Autodesk Fusion 360 part; units mm, degrees
(part 2 of 10)
sketch "10 Node register socket sketch (7) (3)" plane through (0, 0, 5) normal (0, 0, 1) x (1, 0, 0) in component "Panel upper left"
  circle A0 centre (115, 223) radius 1.2
  dimension "d518" = 115
  dimension "d519" = 223
  dimension "d520" = 2.4
  measures "d518" horizontal distance of origin A0.centre
  measures "d519" vertical distance of origin A0.centre
  measures "d520" diameter of A0
extrude "10 Node register socket (7)''" cut sketch "10 Node register socket sketch (7) (3)" against normal blind 1 bodies 3 in component "Panel upper left"
ref_plane "WorkPlane11" through (0, 0, 5) normal (0, 0, 1) x (1, 0, 0) in component "Panel upper left"
sketch "10 Node register socket sketch (8) (3)" plane through (0, 0, 5) normal (0, 0, 1) x (1, 0, 0) in component "Panel upper left"
  circle A0 centre (115, 233) radius 1.2
  dimension "d525" = 115
  dimension "d526" = 233
  dimension "d527" = 2.4
  measures "d525" horizontal distance of origin A0.centre
  measures "d526" vertical distance of origin A0.centre
  measures "d527" diameter of A0
extrude "10 Node register socket (8)''" cut sketch "10 Node register socket sketch (8) (3)" against normal blind 1 bodies 3 in component "Panel upper left"
sketch "01 Panel blank sketch (4)" plane through (0, 0, 0) normal (0, 0, 1) x (1, 0, 0) in component "Panel upper right"
  line L0 (120.1, 120.1) -> (239.9, 120.1)
  line L1 (239.9, 120.1) -> (239.9, 239.9)
  line L2 (239.9, 239.9) -> (120.1, 239.9)
  line L3 (120.1, 239.9) -> (120.1, 120.1)
  dimension "d534" = 120.1
  dimension "d535" = 120.1
  dimension "d536" = 119.8
  dimension "d537" = 119.8
  constraint horizontal L0
  constraint vertical L1
  constraint horizontal L2
  constraint vertical L3
  measures "d534" horizontal distance of origin L0.start
  measures "d535" vertical distance of origin L0.start
  measures "d536" horizontal distance of L0.start L0.end
  measures "d537" vertical distance of L0.end L1.end
extrude "01 Panel blank'''" add sketch "01 Panel blank sketch (4)" along normal blind 5 separate body makes body 4 in component "Panel upper right"
fillet "02 Rounded exterior corners'''" radius 6 1 edges at (239.9, 239.9, 2.5) on bodies 4 in component "Panel upper right"
sketch "03 A main constrained seed (4)" plane through (0, 0, 0) normal (0, 0, 1) x (1, 0, 0) in component "Panel upper right"
  line L0 (147.5, 125) -> (147.5, 135)
  arc A0 (147.5, 135) -> (142.5, 135) centre (145, 135) ccw
  line L1 (142.5, 135) -> (142.5, 125)
  arc A1 (142.5, 125) -> (147.5, 125) centre (145, 125) ccw
  line L2 (145, 125) -> (145, 135) construction
  line L3 (145, 125) -> (155, 125) construction
  dimension "d542" = 5
  dimension "d543" = 10
  dimension "d544" = 90
  dimension "d545" = 10
  dimension "d546" = 145
  dimension "d547" = 125
  constraint tangent L0 A0
  constraint tangent A0 L1
  constraint tangent L1 A1
  constraint tangent L0 A1
  constraint parallel L0 L1
  constraint horizontal L3
  measures "d542" diameter of A0
  measures "d543" distance of A1.centre A0.centre
  measures "d544" angle of L2 L3
  measures "d545" horizontal distance of A1.centre L3.end
  measures "d546" horizontal distance of origin A1.centre
  measures "d547" vertical distance of origin A1.centre
extrude "03 A main through cut'''" cut sketch "03 A main constrained seed (4)" along normal blind 5 bodies 4 in component "Panel upper right"
pattern_linear "03 A main lattice'''" count 4 spacing 20 along (1, 0, 0) count 5 spacing 20 along (0, 1, 0) of "03 A main through cut'''" in component "Panel upper right"
sketch "04 A end strip constrained seed (4)" plane through (0, 0, 0) normal (0, 0, 1) x (1, 0, 0) in component "Panel upper right"
  line L0 (127.5, 145) -> (127.5, 155)
  arc A0 (127.5, 155) -> (122.5, 155) centre (125, 155) ccw
  line L1 (122.5, 155) -> (122.5, 145)
  arc A1 (122.5, 145) -> (127.5, 145) centre (125, 145) ccw
  line L2 (125, 145) -> (125, 155) construction
  line L3 (125, 145) -> (135, 145) construction
  dimension "d554" = 5
  dimension "d555" = 10
  dimension "d556" = 90
  dimension "d557" = 10
  dimension "d558" = 125
  dimension "d559" = 145
  constraint tangent L0 A0
  constraint tangent A0 L1
  constraint tangent L1 A1
  constraint tangent L0 A1
  constraint parallel L0 L1
  constraint horizontal L3
  measures "d554" diameter of A0
  measures "d555" distance of A1.centre A0.centre
  measures "d556" angle of L2 L3
  measures "d557" horizontal distance of A1.centre L3.end
  measures "d558" horizontal distance of origin A1.centre
  measures "d559" vertical distance of origin A1.centre
extrude "04 A end strip through cut'''" cut sketch "04 A end strip constrained seed (4)" along normal blind 5 bodies 4 in component "Panel upper right"
pattern_linear "04 A end strip lattice'''" count 1 spacing 20 along (1, 0, 0) count 3 spacing 20 along (0, 1, 0) of "04 A end strip through cut'''" in component "Panel upper right"
sketch "05 B main constrained seed (4)" plane through (0, 0, 0) normal (0, 0, 1) x (1, 0, 0) in component "Panel upper right"
  line L0 (137.5, 115) -> (137.5, 125)
  arc A0 (137.5, 125) -> (132.5, 125) centre (135, 125) ccw
  line L1 (132.5, 125) -> (132.5, 115)
  arc A1 (132.5, 115) -> (137.5, 115) centre (135, 115) ccw
  line L2 (135, 115) -> (135, 125) construction
  line L3 (135, 115) -> (145, 115) construction
  dimension "d566" = 5
  dimension "d567" = 10
  dimension "d568" = 90
  dimension "d569" = 10
  dimension "d570" = 135
  dimension "d571" = 115
  constraint tangent L0 A0
  constraint tangent A0 L1
  constraint tangent L1 A1
  constraint tangent L0 A1
  constraint parallel L0 L1
  constraint horizontal L3
  measures "d566" diameter of A0
  measures "d567" distance of A1.centre A0.centre
  measures "d568" angle of L2 L3
  measures "d569" horizontal distance of A1.centre L3.end
  measures "d570" horizontal distance of origin A1.centre
  measures "d571" vertical distance of origin A1.centre
extrude "05 B main through cut'''" cut sketch "05 B main constrained seed (4)" along normal blind 5 bodies 4 in component "Panel upper right"
pattern_linear "05 B main lattice'''" count 4 spacing 20 along (1, 0, 0) count 6 spacing 20 along (0, 1, 0) of "05 B main through cut'''" in component "Panel upper right"
sketch "06 B end strip constrained seed (4)" plane through (0, 0, 0) normal (0, 0, 1) x (1, 0, 0) in component "Panel upper right"
  line L0 (217.5, 135) -> (217.5, 145)
  arc A0 (217.5, 145) -> (212.5, 145) centre (215, 145) ccw
  line L1 (212.5, 145) -> (212.5, 135)
  arc A1 (212.5, 135) -> (217.5, 135) centre (215, 135) ccw
  line L2 (215, 135) -> (215, 145) construction
  line L3 (215, 135) -> (225, 135) construction
  dimension "d578" = 5
  dimension "d579" = 10
  dimension "d580" = 90
  dimension "d581" = 10
  dimension "d582" = 215
  dimension "d583" = 135
  constraint tangent L0 A0
  constraint tangent A0 L1
  constraint tangent L1 A1
  constraint tangent L0 A1
  constraint parallel L0 L1
  constraint horizontal L3
  measures "d578" diameter of A0
  measures "d579" distance of A1.centre A0.centre
  measures "d580" angle of L2 L3
  measures "d581" horizontal distance of A1.centre L3.end
  measures "d582" horizontal distance of origin A1.centre
  measures "d583" vertical distance of origin A1.centre
extrude "06 B end strip through cut'''" cut sketch "06 B end strip constrained seed (4)" along normal blind 5 bodies 4 in component "Panel upper right"
pattern_linear "06 B end strip lattice'''" count 1 spacing 20 along (1, 0, 0) count 4 spacing 20 along (0, 1, 0) of "06 B end strip through cut'''" in component "Panel upper right"
sketch "07 Shared node clearance sketch (6)" plane through (0, 0, 0) normal (0, 0, 1) x (1, 0, 0) in component "Panel upper right"
  circle A0 centre (120, 120) radius 4.2
  dimension "d590" = 120
  dimension "d591" = 120
  dimension "d592" = 8.4
  measures "d590" horizontal distance of origin A0.centre
  measures "d591" vertical distance of origin A0.centre
  measures "d592" diameter of A0
extrude "07 Shared node clearance'''" cut sketch "07 Shared node clearance sketch (6)" along normal blind 5 bodies 4 in component "Panel upper right"
sketch "07 Shared node clearance sketch (1) (4)" plane through (0, 0, 0) normal (0, 0, 1) x (1, 0, 0) in component "Panel upper right"
  circle A0 centre (120, 228) radius 4.2
  dimension "d595" = 120
  dimension "d596" = 228
  dimension "d597" = 8.4
  measures "d595" horizontal distance of origin A0.centre
  measures "d596" vertical distance of origin A0.centre
  measures "d597" diameter of A0
extrude "07 Shared node clearance (1)'''" cut sketch "07 Shared node clearance sketch (1) (4)" along normal blind 5 bodies 4 in component "Panel upper right"
sketch "07 Shared node clearance sketch (2) (4)" plane through (0, 0, 0) normal (0, 0, 1) x (1, 0, 0) in component "Panel upper right"
  circle A0 centre (228, 120) radius 4.2
  dimension "d600" = 228
  dimension "d601" = 120
  dimension "d602" = 8.4
  measures "d600" horizontal distance of origin A0.centre
  measures "d601" vertical distance of origin A0.centre
  measures "d602" diameter of A0
extrude "07 Shared node clearance (2)'''" cut sketch "07 Shared node clearance sketch (2) (4)" along normal blind 5 bodies 4 in component "Panel upper right"
sketch "07 Shared node clearance sketch (3) (4)" plane through (0, 0, 0) normal (0, 0, 1) x (1, 0, 0) in component "Panel upper right"
  circle A0 centre (228, 228) radius 4.2
  dimension "d605" = 228
  dimension "d606" = 228
  dimension "d607" = 8.4
  measures "d605" horizontal distance of origin A0.centre
  measures "d606" vertical distance of origin A0.centre
  measures "d607" diameter of A0
extrude "07 Shared node clearance (3)'''" cut sketch "07 Shared node clearance sketch (3) (4)" along normal blind 5 bodies 4 in component "Panel upper right"
fillet "08 Rounded slot entrances and face edges'''" radius 0.4 2 faces at (232.4333, 176.3333, 0) (232.4333, 176.3333, 0) on bodies 4 in component "Panel upper right"
ref_plane "WorkPlane1" through (0, 0, 5) normal (0, 0, 1) x (1, 0, 0) in component "Panel upper right"
sketch "09 Blind rear key socket sketch (4)" plane through (0, 0, 5) normal (0, 0, 1) x (1, 0, 0) in component "Panel upper right"
  circle A0 centre (125, 200) radius 1.7
  dimension "d614" = 125
  dimension "d615" = 200
  dimension "d616" = 3.4
  measures "d614" horizontal distance of origin A0.centre
  measures "d615" vertical distance of origin A0.centre
  measures "d616" diameter of A0
ref_plane "WorkPlane2" through (0, 0, 5) normal (0, 0, 1) x (1, 0, 0) in component "Panel upper right"
sketch "09 Blind rear key socket sketch (1) (4)" plane through (0, 0, 5) normal (0, 0, 1) x (1, 0, 0) in component "Panel upper right"
  circle A0 centre (190, 125) radius 1.7
  dimension "d621" = 190
  dimension "d622" = 125
  dimension "d623" = 3.4
  measures "d621" horizontal distance of origin A0.centre
  measures "d622" vertical distance of origin A0.centre
  measures "d623" diameter of A0
ref_plane "WorkPlane3" through (0, 0, 5) normal (0, 0, 1) x (1, 0, 0) in component "Panel upper right"
sketch "10 Node register socket sketch (11)" plane through (0, 0, 5) normal (0, 0, 1) x (1, 0, 0) in component "Panel upper right"
  circle A0 centre (125, 125) radius 1.2
  dimension "d628" = 125
  dimension "d629" = 125
  dimension "d630" = 2.4
  measures "d628" horizontal distance of origin A0.centre
  measures "d629" vertical distance of origin A0.centre
  measures "d630" diameter of A0
extrude "10 Node register socket'''" cut sketch "10 Node register socket sketch (11)" against normal blind 1 bodies 4 in component "Panel upper right"
ref_plane "WorkPlane4" through (0, 0, 5) normal (0, 0, 1) x (1, 0, 0) in component "Panel upper right"
sketch "10 Node register socket sketch (1) (4)" plane through (0, 0, 5) normal (0, 0, 1) x (1, 0, 0) in component "Panel upper right"
  circle A0 centre (125, 223) radius 1.2
  dimension "d635" = 125
  dimension "d636" = 223
  dimension "d637" = 2.4
  measures "d635" horizontal distance of origin A0.centre
  measures "d636" vertical distance of origin A0.centre
  measures "d637" diameter of A0
extrude "10 Node register socket (1)'''" cut sketch "10 Node register socket sketch (1) (4)" against normal blind 1 bodies 4 in component "Panel upper right"
ref_plane "WorkPlane5" through (0, 0, 5) normal (0, 0, 1) x (1, 0, 0) in component "Panel upper right"
sketch "10 Node register socket sketch (2) (4)" plane through (0, 0, 5) normal (0, 0, 1) x (1, 0, 0) in component "Panel upper right"
  circle A0 centre (125, 233) radius 1.2
  dimension "d642" = 125
  dimension "d643" = 233
  dimension "d644" = 2.4
  measures "d642" horizontal distance of origin A0.centre
  measures "d643" vertical distance of origin A0.centre
  measures "d644" diameter of A0
extrude "10 Node register socket (2)'''" cut sketch "10 Node register socket sketch (2) (4)" against normal blind 1 bodies 4 in component "Panel upper right"
ref_plane "WorkPlane6" through (0, 0, 5) normal (0, 0, 1) x (1, 0, 0) in component "Panel upper right"
sketch "10 Node register socket sketch (3) (4)" plane through (0, 0, 5) normal (0, 0, 1) x (1, 0, 0) in component "Panel upper right"
  circle A0 centre (223, 125) radius 1.2
  dimension "d649" = 223
  dimension "d650" = 125
  dimension "d651" = 2.4
  measures "d649" horizontal distance of origin A0.centre
  measures "d650" vertical distance of origin A0.centre
  measures "d651" diameter of A0
extrude "10 Node register socket (3)'''" cut sketch "10 Node register socket sketch (3) (4)" against normal blind 1 bodies 4 in component "Panel upper right"
ref_plane "WorkPlane7" through (0, 0, 5) normal (0, 0, 1) x (1, 0, 0) in component "Panel upper right"
sketch "10 Node register socket sketch (4) (4)" plane through (0, 0, 5) normal (0, 0, 1) x (1, 0, 0) in component "Panel upper right"
  circle A0 centre (233, 125) radius 1.2
  dimension "d656" = 233
  dimension "d657" = 125
  dimension "d658" = 2.4
  measures "d656" horizontal distance of origin A0.centre
  measures "d657" vertical distance of origin A0.centre
  measures "d658" diameter of A0
extrude "10 Node register socket (4)'''" cut sketch "10 Node register socket sketch (4) (4)" against normal blind 1 bodies 4 in component "Panel upper right"
ref_plane "WorkPlane8" through (0, 0, 5) normal (0, 0, 1) x (1, 0, 0) in component "Panel upper right"
sketch "10 Node register socket sketch (5) (4)" plane through (0, 0, 5) normal (0, 0, 1) x (1, 0, 0) in component "Panel upper right"
  circle A0 centre (223, 223) radius 1.2
  dimension "d663" = 223
  dimension "d664" = 223
  dimension "d665" = 2.4
  measures "d663" horizontal distance of origin A0.centre
  measures "d664" vertical distance of origin A0.centre
  measures "d665" diameter of A0
extrude "10 Node register socket (5)'''" cut sketch "10 Node register socket sketch (5) (4)" against normal blind 1 bodies 4 in component "Panel upper right"
ref_plane "WorkPlane9" through (0, 0, 5) normal (0, 0, 1) x (1, 0, 0) in component "Panel upper right"
sketch "10 Node register socket sketch (6) (4)" plane through (0, 0, 5) normal (0, 0, 1) x (1, 0, 0) in component "Panel upper right"
  circle A0 centre (223, 233) radius 1.2
  dimension "d670" = 223
  dimension "d671" = 233
  dimension "d672" = 2.4
  measures "d670" horizontal distance of origin A0.centre
  measures "d671" vertical distance of origin A0.centre
  measures "d672" diameter of A0
extrude "10 Node register socket (6)'''" cut sketch "10 Node register socket sketch (6) (4)" against normal blind 1 bodies 4 in component "Panel upper right"
ref_plane "WorkPlane10" through (0, 0, 5) normal (0, 0, 1) x (1, 0, 0) in component "Panel upper right"
sketch "10 Node register socket sketch (7) (4)" plane through (0, 0, 5) normal (0, 0, 1) x (1, 0, 0) in component "Panel upper right"
  circle A0 centre (233, 223) radius 1.2
  dimension "d677" = 233
  dimension "d678" = 223
  dimension "d679" = 2.4
  measures "d677" horizontal distance of origin A0.centre
  measures "d678" vertical distance of origin A0.centre
  measures "d679" diameter of A0
extrude "10 Node register socket (7)'''" cut sketch "10 Node register socket sketch (7) (4)" against normal blind 1 bodies 4 in component "Panel upper right"
ref_plane "WorkPlane11" through (0, 0, 5) normal (0, 0, 1) x (1, 0, 0) in component "Panel upper right"
sketch "10 Node register socket sketch (8) (4)" plane through (0, 0, 5) normal (0, 0, 1) x (1, 0, 0) in component "Panel upper right"
  circle A0 centre (233, 233) radius 1.2
  dimension "d684" = 233
  dimension "d685" = 233
  dimension "d686" = 2.4
  measures "d684" horizontal distance of origin A0.centre
  measures "d685" vertical distance of origin A0.centre
  measures "d686" diameter of A0
extrude "10 Node register socket (8)'''" cut sketch "10 Node register socket sketch (8) (4)" against normal blind 1 bodies 4 in component "Panel upper right"
ref_plane "WorkPlane1" through (0, 2, 0) normal (0, 1, 0) x (0, 0, 1) in component "Vertical rail 0 - measured sloped-slot approximation"
sketch "Profile blank sketch" plane through (0, 2, 0) normal (0, 1, 0) x (1, 0, 0) in component "Vertical rail 0 - measured sloped-slot approximation"
  line L0 (2, -15) -> (22, -15)
  line L1 (22, -15) -> (22, -35)
  line L2 (22, -35) -> (2, -35)
  line L3 (2, -35) -> (2, -15)
  dimension "d701" = 2
  dimension "d702" = 15
  dimension "d703" = 22
  dimension "d704" = 35
  constraint horizontal L0.start L0.end
  constraint vertical L0.end L1.end
  constraint vertical L0.start L2.end
  constraint horizontal L1.end L2.end
  measures "d701" horizontal distance of origin L0.start
  measures "d702" vertical distance of origin L0.start
  measures "d703" horizontal distance of origin L0.end
  measures "d704" vertical distance of origin L1.end
extrude "Profile blank" add sketch "Profile blank sketch" along normal blind 236 separate body makes body 5 in component "Vertical rail 0 - measured sloped-slot approximation"
ref_plane "WorkPlane2" through (0, 2, 0) normal (0, 1, 0) x (0, 0, 1) in component "Vertical rail 0 - measured sloped-slot approximation"
sketch "Sloped T channel 0 sketch" plane through (0, 2, 0) normal (0, 1, 0) x (1, 0, 0) in component "Vertical rail 0 - measured sloped-slot approximation"
  line L0 (8.86, -15) -> (8.86, -16.5)
  line L1 (8.86, -16.5) -> (6.5, -16.5)
  line L2 (6.5, -16.5) -> (6.5, -18.55)
  line L3 (6.5, -18.55) -> (9.15, -21.2)
  line L4 (9.15, -21.2) -> (14.85, -21.2)
  line L5 (14.85, -21.2) -> (17.5, -18.55)
  line L6 (17.5, -18.55) -> (17.5, -16.5)
  line L7 (17.5, -16.5) -> (15.14, -16.5)
  line L8 (15.14, -16.5) -> (15.14, -15)
  line L9 (15.14, -15) -> (8.86, -15)
  dimension "d709" = 8.86
  dimension "d710" = 15
  dimension "d711" = 16.5
  dimension "d712" = 6.5
  dimension "d713" = 18.55
  dimension "d714" = 9.15
  dimension "d715" = 21.2
  dimension "d716" = 14.85
  dimension "d717" = 17.5
  dimension "d718" = 15.14
  constraint vertical L0.start L0.end
  constraint horizontal L0.end L1.end
  constraint vertical L1.end L2.end
  constraint horizontal L3.end L4.end
  constraint horizontal L2.end L5.end
  constraint vertical L5.end L6.end
  constraint horizontal L1.end L6.end
  constraint horizontal L6.end L7.end
  constraint vertical L7.end L8.end
  constraint horizontal L0.start L8.end
  measures "d709" horizontal distance of origin L0.start
  measures "d710" vertical distance of origin L0.start
  measures "d711" vertical distance of origin L0.end
  measures "d712" horizontal distance of origin L1.end
  measures "d713" vertical distance of origin L2.end
  measures "d714" horizontal distance of origin L3.end
  measures "d715" vertical distance of origin L3.end
  measures "d716" horizontal distance of origin L4.end
  measures "d717" horizontal distance of origin L5.end
  measures "d718" horizontal distance of origin L7.end
extrude "Sloped T channel 0" cut sketch "Sloped T channel 0 sketch" along normal blind 236 bodies 5 in component "Vertical rail 0 - measured sloped-slot approximation"
ref_plane "WorkPlane3" through (0, 2, 0) normal (0, 1, 0) x (0, 0, 1) in component "Vertical rail 0 - measured sloped-slot approximation"
sketch "Sloped T channel 1 sketch" plane through (0, 2, 0) normal (0, 1, 0) x (1, 0, 0) in component "Vertical rail 0 - measured sloped-slot approximation"
  line L0 (22, -21.86) -> (20.5, -21.86)
  line L1 (20.5, -21.86) -> (20.5, -19.5)
  line L2 (20.5, -19.5) -> (18.45, -19.5)
  line L3 (18.45, -19.5) -> (15.8, -22.15)
  line L4 (15.8, -22.15) -> (15.8, -27.85)
  line L5 (15.8, -27.85) -> (18.45, -30.5)
  line L6 (18.45, -30.5) -> (20.5, -30.5)
  line L7 (20.5, -30.5) -> (20.5, -28.14)
  line L8 (20.5, -28.14) -> (22, -28.14)
  line L9 (22, -28.14) -> (22, -21.86)
  dimension "d723" = 22
  dimension "d724" = 21.86
  dimension "d725" = 20.5
  dimension "d726" = 19.5
  dimension "d727" = 18.45
  dimension "d728" = 15.8
  dimension "d729" = 22.15
  dimension "d730" = 27.85
  dimension "d731" = 30.5
  dimension "d732" = 28.14
  constraint horizontal L0.start L0.end
  constraint vertical L0.end L1.end
  constraint horizontal L1.end L2.end
  constraint vertical L3.end L4.end
  constraint vertical L2.end L5.end
  constraint vertical L1.end L6.end
  constraint horizontal L5.end L6.end
  constraint vertical L6.end L7.end
  constraint vertical L0.start L8.end
  constraint horizontal L7.end L8.end
  measures "d723" horizontal distance of origin L0.start
  measures "d724" vertical distance of origin L0.start
  measures "d725" horizontal distance of origin L0.end
  measures "d726" vertical distance of origin L1.end
  measures "d727" horizontal distance of origin L2.end
  measures "d728" horizontal distance of origin L3.end
  measures "d729" vertical distance of origin L3.end
  measures "d730" vertical distance of origin L4.end
  measures "d731" vertical distance of origin L5.end
  measures "d732" vertical distance of origin L7.end
extrude "Sloped T channel 1" cut sketch "Sloped T channel 1 sketch" along normal blind 236 bodies 5 in component "Vertical rail 0 - measured sloped-slot approximation"
ref_plane "WorkPlane4" through (0, 2, 0) normal (0, 1, 0) x (0, 0, 1) in component "Vertical rail 0 - measured sloped-slot approximation"
sketch "Sloped T channel 2 sketch" plane through (0, 2, 0) normal (0, 1, 0) x (1, 0, 0) in component "Vertical rail 0 - measured sloped-slot approximation"
  line L0 (15.14, -35) -> (15.14, -33.5)
  line L1 (15.14, -33.5) -> (17.5, -33.5)
  line L2 (17.5, -33.5) -> (17.5, -31.45)
  line L3 (17.5, -31.45) -> (14.85, -28.8)
  line L4 (14.85, -28.8) -> (9.15, -28.8)
  line L5 (9.15, -28.8) -> (6.5, -31.45)
  line L6 (6.5, -31.45) -> (6.5, -33.5)
  line L7 (6.5, -33.5) -> (8.86, -33.5)
  line L8 (8.86, -33.5) -> (8.86, -35)
  line L9 (8.86, -35) -> (15.14, -35)
  dimension "d737" = 15.14
  dimension "d738" = 35
  dimension "d739" = 33.5
  dimension "d740" = 17.5
  dimension "d741" = 31.45
  dimension "d742" = 14.85
  dimension "d743" = 28.8
  dimension "d744" = 9.15
  dimension "d745" = 6.5
  dimension "d746" = 8.86
  constraint vertical L0.start L0.end
  constraint horizontal L0.end L1.end
  constraint vertical L1.end L2.end
  constraint horizontal L3.end L4.end
  constraint horizontal L2.end L5.end
  constraint vertical L5.end L6.end
  constraint horizontal L1.end L6.end
  constraint horizontal L6.end L7.end
  constraint vertical L7.end L8.end
  constraint horizontal L0.start L8.end
  measures "d737" horizontal distance of origin L0.start
  measures "d738" vertical distance of origin L0.start
  measures "d739" vertical distance of origin L0.end
  measures "d740" horizontal distance of origin L1.end
  measures "d741" vertical distance of origin L2.end
  measures "d742" horizontal distance of origin L3.end
  measures "d743" vertical distance of origin L3.end
  measures "d744" horizontal distance of origin L4.end
  measures "d745" horizontal distance of origin L5.end
  measures "d746" horizontal distance of origin L7.end
extrude "Sloped T channel 2" cut sketch "Sloped T channel 2 sketch" along normal blind 236 bodies 5 in component "Vertical rail 0 - measured sloped-slot approximation"
ref_plane "WorkPlane5" through (0, 2, 0) normal (0, 1, 0) x (0, 0, 1) in component "Vertical rail 0 - measured sloped-slot approximation"
sketch "Sloped T channel 3 sketch" plane through (0, 2, 0) normal (0, 1, 0) x (1, 0, 0) in component "Vertical rail 0 - measured sloped-slot approximation"
  line L0 (2, -28.14) -> (3.5, -28.14)
  line L1 (3.5, -28.14) -> (3.5, -30.5)
  line L2 (3.5, -30.5) -> (5.55, -30.5)
  line L3 (5.55, -30.5) -> (8.2, -27.85)
  line L4 (8.2, -27.85) -> (8.2, -22.15)
  line L5 (8.2, -22.15) -> (5.55, -19.5)
  line L6 (5.55, -19.5) -> (3.5, -19.5)
  line L7 (3.5, -19.5) -> (3.5, -21.86)
  line L8 (3.5, -21.86) -> (2, -21.86)
  line L9 (2, -21.86) -> (2, -28.14)
  dimension "d751" = 2
  dimension "d752" = 28.14
  dimension "d753" = 3.5
  dimension "d754" = 30.5
  dimension "d755" = 5.55
  dimension "d756" = 8.2
  dimension "d757" = 27.85
  dimension "d758" = 22.15
  dimension "d759" = 19.5
  dimension "d760" = 21.86
  constraint horizontal L0.start L0.end
  constraint vertical L0.end L1.end
  constraint horizontal L1.end L2.end
  constraint vertical L3.end L4.end
  constraint vertical L2.end L5.end
  constraint vertical L1.end L6.end
  constraint horizontal L5.end L6.end
  constraint vertical L6.end L7.end
  constraint vertical L0.start L8.end
  constraint horizontal L7.end L8.end
  measures "d751" horizontal distance of origin L0.start
  measures "d752" vertical distance of origin L0.start
  measures "d753" horizontal distance of origin L0.end
  measures "d754" vertical distance of origin L1.end
  measures "d755" horizontal distance of origin L2.end
  measures "d756" horizontal distance of origin L3.end
  measures "d757" vertical distance of origin L3.end
  measures "d758" vertical distance of origin L4.end
  measures "d759" vertical distance of origin L5.end
  measures "d760" vertical distance of origin L7.end
extrude "Sloped T channel 3" cut sketch "Sloped T channel 3 sketch" along normal blind 236 bodies 5 in component "Vertical rail 0 - measured sloped-slot approximation"
ref_plane "WorkPlane6" through (0, 2, 0) normal (0, 1, 0) x (0, 0, 1) in component "Vertical rail 0 - measured sloped-slot approximation"
sketch "Reference center bore sketch" plane through (0, 2, 0) normal (0, 1, 0) x (1, 0, 0) in component "Vertical rail 0 - measured sloped-slot approximation"
  circle A0 centre (12, -25) radius 2.5
  dimension "d765" = 12
  dimension "d766" = 25
  dimension "d767" = 5
  measures "d765" horizontal distance of origin A0.centre
  measures "d766" vertical distance of origin A0.centre
  measures "d767" diameter of A0
extrude "Reference center bore" cut sketch "Reference center bore sketch" along normal blind 236 bodies 5 in component "Vertical rail 0 - measured sloped-slot approximation"
ref_plane "WorkPlane1" through (0, 2, 0) normal (0, 1, 0) x (0, 0, 1) in component "Vertical rail 1 - measured sloped-slot approximation"
sketch "Profile blank sketch (2)" plane through (0, 2, 0) normal (0, 1, 0) x (1, 0, 0) in component "Vertical rail 1 - measured sloped-slot approximation"
  line L0 (110, -15) -> (130, -15)
  line L1 (130, -15) -> (130, -35)
  line L2 (130, -35) -> (110, -35)
  line L3 (110, -35) -> (110, -15)
  dimension "d772" = 110
  dimension "d773" = 15
  dimension "d774" = 130
  dimension "d775" = 35
  constraint horizontal L0.start L0.end
  constraint vertical L0.end L1.end
  constraint vertical L0.start L2.end
  constraint horizontal L1.end L2.end
  measures "d772" horizontal distance of origin L0.start
  measures "d773" vertical distance of origin L0.start
  measures "d774" horizontal distance of origin L0.end
  measures "d775" vertical distance of origin L1.end
extrude "Profile blank'" add sketch "Profile blank sketch (2)" along normal blind 236 separate body makes body 6 in component "Vertical rail 1 - measured sloped-slot approximation"
ref_plane "WorkPlane2" through (0, 2, 0) normal (0, 1, 0) x (0, 0, 1) in component "Vertical rail 1 - measured sloped-slot approximation"
sketch "Sloped T channel 0 sketch (2)" plane through (0, 2, 0) normal (0, 1, 0) x (1, 0, 0) in component "Vertical rail 1 - measured sloped-slot approximation"
  line L0 (116.86, -15) -> (116.86, -16.5)
  line L1 (116.86, -16.5) -> (114.5, -16.5)
  line L2 (114.5, -16.5) -> (114.5, -18.55)
  line L3 (114.5, -18.55) -> (117.15, -21.2)
  line L4 (117.15, -21.2) -> (122.85, -21.2)
  line L5 (122.85, -21.2) -> (125.5, -18.55)
  line L6 (125.5, -18.55) -> (125.5, -16.5)
  line L7 (125.5, -16.5) -> (123.14, -16.5)
  line L8 (123.14, -16.5) -> (123.14, -15)
  line L9 (123.14, -15) -> (116.86, -15)
  dimension "d780" = 116.86
  dimension "d781" = 15
  dimension "d782" = 16.5
  dimension "d783" = 114.5
  dimension "d784" = 18.55
  dimension "d785" = 117.15
  dimension "d786" = 21.2
  dimension "d787" = 122.85
  dimension "d788" = 125.5
  dimension "d789" = 123.14
  constraint vertical L0.start L0.end
  constraint horizontal L0.end L1.end
  constraint vertical L1.end L2.end
  constraint horizontal L3.end L4.end
  constraint horizontal L2.end L5.end
  constraint vertical L5.end L6.end
  constraint horizontal L1.end L6.end
  constraint horizontal L6.end L7.end
  constraint vertical L7.end L8.end
  constraint horizontal L0.start L8.end
  measures "d780" horizontal distance of origin L0.start
  measures "d781" vertical distance of origin L0.start
  measures "d782" vertical distance of origin L0.end
  measures "d783" horizontal distance of origin L1.end
  measures "d784" vertical distance of origin L2.end
  measures "d785" horizontal distance of origin L3.end
  measures "d786" vertical distance of origin L3.end
  measures "d787" horizontal distance of origin L4.end
  measures "d788" horizontal distance of origin L5.end
  measures "d789" horizontal distance of origin L7.end
extrude "Sloped T channel 0'" cut sketch "Sloped T channel 0 sketch (2)" along normal blind 236 bodies 6 in component "Vertical rail 1 - measured sloped-slot approximation"
ref_plane "WorkPlane3" through (0, 2, 0) normal (0, 1, 0) x (0, 0, 1) in component "Vertical rail 1 - measured sloped-slot approximation"
sketch "Sloped T channel 1 sketch (2)" plane through (0, 2, 0) normal (0, 1, 0) x (1, 0, 0) in component "Vertical rail 1 - measured sloped-slot approximation"
  line L0 (130, -21.86) -> (128.5, -21.86)
  line L1 (128.5, -21.86) -> (128.5, -19.5)
  line L2 (128.5, -19.5) -> (126.45, -19.5)
  line L3 (126.45, -19.5) -> (123.8, -22.15)
  line L4 (123.8, -22.15) -> (123.8, -27.85)
  line L5 (123.8, -27.85) -> (126.45, -30.5)
  line L6 (126.45, -30.5) -> (128.5, -30.5)
  line L7 (128.5, -30.5) -> (128.5, -28.14)
  line L8 (128.5, -28.14) -> (130, -28.14)
  line L9 (130, -28.14) -> (130, -21.86)
  dimension "d794" = 130
  dimension "d795" = 21.86
  dimension "d796" = 128.5
  dimension "d797" = 19.5
  dimension "d798" = 126.45
  dimension "d799" = 123.8
  dimension "d800" = 22.15
  dimension "d801" = 27.85
  dimension "d802" = 30.5
  dimension "d803" = 28.14
  constraint horizontal L0.start L0.end
  constraint vertical L0.end L1.end
  constraint horizontal L1.end L2.end
  constraint vertical L3.end L4.end
  constraint vertical L2.end L5.end
  constraint vertical L1.end L6.end
  constraint horizontal L5.end L6.end
  constraint vertical L6.end L7.end
  constraint vertical L0.start L8.end
  constraint horizontal L7.end L8.end
  measures "d794" horizontal distance of origin L0.start
  measures "d795" vertical distance of origin L0.start
  measures "d796" horizontal distance of origin L0.end
  measures "d797" vertical distance of origin L1.end
  measures "d798" horizontal distance of origin L2.end
  measures "d799" horizontal distance of origin L3.end
  measures "d800" vertical distance of origin L3.end
  measures "d801" vertical distance of origin L4.end
  measures "d802" vertical distance of origin L5.end
  measures "d803" vertical distance of origin L7.end
extrude "Sloped T channel 1'" cut sketch "Sloped T channel 1 sketch (2)" along normal blind 236 bodies 6 in component "Vertical rail 1 - measured sloped-slot approximation"
ref_plane "WorkPlane4" through (0, 2, 0) normal (0, 1, 0) x (0, 0, 1) in component "Vertical rail 1 - measured sloped-slot approximation"
sketch "Sloped T channel 2 sketch (2)" plane through (0, 2, 0) normal (0, 1, 0) x (1, 0, 0) in component "Vertical rail 1 - measured sloped-slot approximation"
  line L0 (123.14, -35) -> (123.14, -33.5)
  line L1 (123.14, -33.5) -> (125.5, -33.5)
  line L2 (125.5, -33.5) -> (125.5, -31.45)
  line L3 (125.5, -31.45) -> (122.85, -28.8)
  line L4 (122.85, -28.8) -> (117.15, -28.8)
  line L5 (117.15, -28.8) -> (114.5, -31.45)
  line L6 (114.5, -31.45) -> (114.5, -33.5)
  line L7 (114.5, -33.5) -> (116.86, -33.5)
  line L8 (116.86, -33.5) -> (116.86, -35)
  line L9 (116.86, -35) -> (123.14, -35)
  dimension "d808" = 123.14
  dimension "d809" = 35
  dimension "d810" = 33.5
  dimension "d811" = 125.5
  dimension "d812" = 31.45
  dimension "d813" = 122.85
  dimension "d814" = 28.8
  dimension "d815" = 117.15
  dimension "d816" = 114.5
  dimension "d817" = 116.86
  constraint vertical L0.start L0.end
  constraint horizontal L0.end L1.end
  constraint vertical L1.end L2.end
  constraint horizontal L3.end L4.end
  constraint horizontal L2.end L5.end
  constraint vertical L5.end L6.end
  constraint horizontal L1.end L6.end
  constraint horizontal L6.end L7.end
  constraint vertical L7.end L8.end
  constraint horizontal L0.start L8.end
  measures "d808" horizontal distance of origin L0.start
  measures "d809" vertical distance of origin L0.start
  measures "d810" vertical distance of origin L0.end
  measures "d811" horizontal distance of origin L1.end
  measures "d812" vertical distance of origin L2.end
  measures "d813" horizontal distance of origin L3.end
  measures "d814" vertical distance of origin L3.end
  measures "d815" horizontal distance of origin L4.end
  measures "d816" horizontal distance of origin L5.end
  measures "d817" horizontal distance of origin L7.end
extrude "Sloped T channel 2'" cut sketch "Sloped T channel 2 sketch (2)" along normal blind 236 bodies 6 in component "Vertical rail 1 - measured sloped-slot approximation"
ref_plane "WorkPlane5" through (0, 2, 0) normal (0, 1, 0) x (0, 0, 1) in component "Vertical rail 1 - measured sloped-slot approximation"
sketch "Sloped T channel 3 sketch (2)" plane through (0, 2, 0) normal (0, 1, 0) x (1, 0, 0) in component "Vertical rail 1 - measured sloped-slot approximation"
  line L0 (110, -28.14) -> (111.5, -28.14)
  line L1 (111.5, -28.14) -> (111.5, -30.5)
  line L2 (111.5, -30.5) -> (113.55, -30.5)
  line L3 (113.55, -30.5) -> (116.2, -27.85)
  line L4 (116.2, -27.85) -> (116.2, -22.15)
  line L5 (116.2, -22.15) -> (113.55, -19.5)
  line L6 (113.55, -19.5) -> (111.5, -19.5)
  line L7 (111.5, -19.5) -> (111.5, -21.86)
  line L8 (111.5, -21.86) -> (110, -21.86)
  line L9 (110, -21.86) -> (110, -28.14)
  dimension "d822" = 110
  dimension "d823" = 28.14
  dimension "d824" = 111.5
  dimension "d825" = 30.5
  dimension "d826" = 113.55
  dimension "d827" = 116.2
  dimension "d828" = 27.85
  dimension "d829" = 22.15
  dimension "d830" = 19.5
  dimension "d831" = 21.86
  constraint horizontal L0.start L0.end
  constraint vertical L0.end L1.end
  constraint horizontal L1.end L2.end
  constraint vertical L3.end L4.end
  constraint vertical L2.end L5.end
  constraint vertical L1.end L6.end
  constraint horizontal L5.end L6.end
  constraint vertical L6.end L7.end
  constraint vertical L0.start L8.end
  constraint horizontal L7.end L8.end
  measures "d822" horizontal distance of origin L0.start
  measures "d823" vertical distance of origin L0.start
  measures "d824" horizontal distance of origin L0.end
  measures "d825" vertical distance of origin L1.end
  measures "d826" horizontal distance of origin L2.end
  measures "d827" horizontal distance of origin L3.end
  measures "d828" vertical distance of origin L3.end
  measures "d829" vertical distance of origin L4.end
  measures "d830" vertical distance of origin L5.end
  measures "d831" vertical distance of origin L7.end
extrude "Sloped T channel 3'" cut sketch "Sloped T channel 3 sketch (2)" along normal blind 236 bodies 6 in component "Vertical rail 1 - measured sloped-slot approximation"
ref_plane "WorkPlane6" through (0, 2, 0) normal (0, 1, 0) x (0, 0, 1) in component "Vertical rail 1 - measured sloped-slot approximation"
sketch "Reference center bore sketch (2)" plane through (0, 2, 0) normal (0, 1, 0) x (1, 0, 0) in component "Vertical rail 1 - measured sloped-slot approximation"
  circle A0 centre (120, -25) radius 2.5
  dimension "d836" = 120
  dimension "d837" = 25
  dimension "d838" = 5
  measures "d836" horizontal distance of origin A0.centre
  measures "d837" vertical distance of origin A0.centre
  measures "d838" diameter of A0
extrude "Reference center bore'" cut sketch "Reference center bore sketch (2)" along normal blind 236 bodies 6 in component "Vertical rail 1 - measured sloped-slot approximation"
ref_plane "WorkPlane1" through (0, 2, 0) normal (0, 1, 0) x (0, 0, 1) in component "Vertical rail 2 - measured sloped-slot approximation"
sketch "Profile blank sketch (3)" plane through (0, 2, 0) normal (0, 1, 0) x (1, 0, 0) in component "Vertical rail 2 - measured sloped-slot approximation"
  line L0 (218, -15) -> (238, -15)
  line L1 (238, -15) -> (238, -35)
  line L2 (238, -35) -> (218, -35)
  line L3 (218, -35) -> (218, -15)
  dimension "d843" = 218
  dimension "d844" = 15
  dimension "d845" = 238
  dimension "d846" = 35
  constraint horizontal L0.start L0.end
  constraint vertical L0.end L1.end
  constraint vertical L0.start L2.end
  constraint horizontal L1.end L2.end
  measures "d843" horizontal distance of origin L0.start
  measures "d844" vertical distance of origin L0.start
  measures "d845" horizontal distance of origin L0.end
  measures "d846" vertical distance of origin L1.end
extrude "Profile blank''" add sketch "Profile blank sketch (3)" along normal blind 236 separate body makes body 7 in component "Vertical rail 2 - measured sloped-slot approximation"
ref_plane "WorkPlane2" through (0, 2, 0) normal (0, 1, 0) x (0, 0, 1) in component "Vertical rail 2 - measured sloped-slot approximation"
sketch "Sloped T channel 0 sketch (3)" plane through (0, 2, 0) normal (0, 1, 0) x (1, 0, 0) in component "Vertical rail 2 - measured sloped-slot approximation"
  line L0 (224.86, -15) -> (224.86, -16.5)
  line L1 (224.86, -16.5) -> (222.5, -16.5)
  line L2 (222.5, -16.5) -> (222.5, -18.55)
  line L3 (222.5, -18.55) -> (225.15, -21.2)
  line L4 (225.15, -21.2) -> (230.85, -21.2)
  line L5 (230.85, -21.2) -> (233.5, -18.55)
  line L6 (233.5, -18.55) -> (233.5, -16.5)
  line L7 (233.5, -16.5) -> (231.14, -16.5)
  line L8 (231.14, -16.5) -> (231.14, -15)
  line L9 (231.14, -15) -> (224.86, -15)
  dimension "d851" = 224.86
  dimension "d852" = 15
  dimension "d853" = 16.5
  dimension "d854" = 222.5
  dimension "d855" = 18.55
  dimension "d856" = 225.15
  dimension "d857" = 21.2
  dimension "d858" = 230.85
  dimension "d859" = 233.5
  dimension "d860" = 231.14
  constraint vertical L0.start L0.end
  constraint horizontal L0.end L1.end
  constraint vertical L1.end L2.end
  constraint horizontal L3.end L4.end
  constraint horizontal L2.end L5.end
  constraint vertical L5.end L6.end
  constraint horizontal L1.end L6.end
  constraint horizontal L6.end L7.end
  constraint vertical L7.end L8.end
  constraint horizontal L0.start L8.end
  measures "d851" horizontal distance of origin L0.start
  measures "d852" vertical distance of origin L0.start
  measures "d853" vertical distance of origin L0.end
  measures "d854" horizontal distance of origin L1.end
  measures "d855" vertical distance of origin L2.end
  measures "d856" horizontal distance of origin L3.end
  measures "d857" vertical distance of origin L3.end
  measures "d858" horizontal distance of origin L4.end
  measures "d859" horizontal distance of origin L5.end
  measures "d860" horizontal distance of origin L7.end
extrude "Sloped T channel 0''" cut sketch "Sloped T channel 0 sketch (3)" along normal blind 236 bodies 7 in component "Vertical rail 2 - measured sloped-slot approximation"
ref_plane "WorkPlane3" through (0, 2, 0) normal (0, 1, 0) x (0, 0, 1) in component "Vertical rail 2 - measured sloped-slot approximation"
sketch "Sloped T channel 1 sketch (3)" plane through (0, 2, 0) normal (0, 1, 0) x (1, 0, 0) in component "Vertical rail 2 - measured sloped-slot approximation"
  line L0 (238, -21.86) -> (236.5, -21.86)
  line L1 (236.5, -21.86) -> (236.5, -19.5)
  line L2 (236.5, -19.5) -> (234.45, -19.5)
  line L3 (234.45, -19.5) -> (231.8, -22.15)
  line L4 (231.8, -22.15) -> (231.8, -27.85)
  line L5 (231.8, -27.85) -> (234.45, -30.5)
  line L6 (234.45, -30.5) -> (236.5, -30.5)
  line L7 (236.5, -30.5) -> (236.5, -28.14)
  line L8 (236.5, -28.14) -> (238, -28.14)
  line L9 (238, -28.14) -> (238, -21.86)
  dimension "d865" = 238
  dimension "d866" = 21.86
  dimension "d867" = 236.5
  dimension "d868" = 19.5
  dimension "d869" = 234.45
  dimension "d870" = 231.8
  dimension "d871" = 22.15
  dimension "d872" = 27.85
  dimension "d873" = 30.5
  dimension "d874" = 28.14
  constraint horizontal L0.start L0.end
  constraint vertical L0.end L1.end
  constraint horizontal L1.end L2.end
  constraint vertical L3.end L4.end
  constraint vertical L2.end L5.end
  constraint vertical L1.end L6.end
  constraint horizontal L5.end L6.end
  constraint vertical L6.end L7.end
  constraint vertical L0.start L8.end
  constraint horizontal L7.end L8.end
  measures "d865" horizontal distance of origin L0.start
  measures "d866" vertical distance of origin L0.start
  measures "d867" horizontal distance of origin L0.end
  measures "d868" vertical distance of origin L1.end
  measures "d869" horizontal distance of origin L2.end
  measures "d870" horizontal distance of origin L3.end
  measures "d871" vertical distance of origin L3.end
  measures "d872" vertical distance of origin L4.end
  measures "d873" vertical distance of origin L5.end
  measures "d874" vertical distance of origin L7.end
extrude "Sloped T channel 1''" cut sketch "Sloped T channel 1 sketch (3)" along normal blind 236 bodies 7 in component "Vertical rail 2 - measured sloped-slot approximation"
ref_plane "WorkPlane4" through (0, 2, 0) normal (0, 1, 0) x (0, 0, 1) in component "Vertical rail 2 - measured sloped-slot approximation"
sketch "Sloped T channel 2 sketch (3)" plane through (0, 2, 0) normal (0, 1, 0) x (1, 0, 0) in component "Vertical rail 2 - measured sloped-slot approximation"
  line L0 (231.14, -35) -> (231.14, -33.5)
  line L1 (231.14, -33.5) -> (233.5, -33.5)
  line L2 (233.5, -33.5) -> (233.5, -31.45)
  line L3 (233.5, -31.45) -> (230.85, -28.8)
  line L4 (230.85, -28.8) -> (225.15, -28.8)
  line L5 (225.15, -28.8) -> (222.5, -31.45)
  line L6 (222.5, -31.45) -> (222.5, -33.5)
  line L7 (222.5, -33.5) -> (224.86, -33.5)
  line L8 (224.86, -33.5) -> (224.86, -35)
  line L9 (224.86, -35) -> (231.14, -35)
  dimension "d879" = 231.14
  dimension "d880" = 35
  dimension "d881" = 33.5
  dimension "d882" = 233.5
  dimension "d883" = 31.45
  dimension "d884" = 230.85
  dimension "d885" = 28.8
  dimension "d886" = 225.15
  dimension "d887" = 222.5
  dimension "d888" = 224.86
  constraint vertical L0.start L0.end
  constraint horizontal L0.end L1.end
  constraint vertical L1.end L2.end
  constraint horizontal L3.end L4.end
  constraint horizontal L2.end L5.end
  constraint vertical L5.end L6.end
  constraint horizontal L1.end L6.end
  constraint horizontal L6.end L7.end
  constraint vertical L7.end L8.end
  constraint horizontal L0.start L8.end
  measures "d879" horizontal distance of origin L0.start
  measures "d880" vertical distance of origin L0.start
  measures "d881" vertical distance of origin L0.end
  measures "d882" horizontal distance of origin L1.end
  measures "d883" vertical distance of origin L2.end
  measures "d884" horizontal distance of origin L3.end
  measures "d885" vertical distance of origin L3.end
  measures "d886" horizontal distance of origin L4.end
  measures "d887" horizontal distance of origin L5.end
  measures "d888" horizontal distance of origin L7.end
extrude "Sloped T channel 2''" cut sketch "Sloped T channel 2 sketch (3)" along normal blind 236 bodies 7 in component "Vertical rail 2 - measured sloped-slot approximation"
ref_plane "WorkPlane5" through (0, 2, 0) normal (0, 1, 0) x (0, 0, 1) in component "Vertical rail 2 - measured sloped-slot approximation"
sketch "Sloped T channel 3 sketch (3)" plane through (0, 2, 0) normal (0, 1, 0) x (1, 0, 0) in component "Vertical rail 2 - measured sloped-slot approximation"
  line L0 (218, -28.14) -> (219.5, -28.14)
  line L1 (219.5, -28.14) -> (219.5, -30.5)
  line L2 (219.5, -30.5) -> (221.55, -30.5)
  line L3 (221.55, -30.5) -> (224.2, -27.85)
  line L4 (224.2, -27.85) -> (224.2, -22.15)
  line L5 (224.2, -22.15) -> (221.55, -19.5)
  line L6 (221.55, -19.5) -> (219.5, -19.5)
  line L7 (219.5, -19.5) -> (219.5, -21.86)
  line L8 (219.5, -21.86) -> (218, -21.86)
  line L9 (218, -21.86) -> (218, -28.14)
  dimension "d893" = 218
  dimension "d894" = 28.14
  dimension "d895" = 219.5
  dimension "d896" = 30.5
  dimension "d897" = 221.55
  dimension "d898" = 224.2
  dimension "d899" = 27.85
  dimension "d900" = 22.15
  dimension "d901" = 19.5
  dimension "d902" = 21.86
  constraint horizontal L0.start L0.end
  constraint vertical L0.end L1.end
  constraint horizontal L1.end L2.end
  constraint vertical L3.end L4.end
  constraint vertical L2.end L5.end
  constraint vertical L1.end L6.end
  constraint horizontal L5.end L6.end
  constraint vertical L6.end L7.end
  constraint vertical L0.start L8.end
  constraint horizontal L7.end L8.end
  measures "d893" horizontal distance of origin L0.start
  measures "d894" vertical distance of origin L0.start
  measures "d895" horizontal distance of origin L0.end
  measures "d896" vertical distance of origin L1.end
  measures "d897" horizontal distance of origin L2.end
  measures "d898" horizontal distance of origin L3.end
  measures "d899" vertical distance of origin L3.end
  measures "d900" vertical distance of origin L4.end
  measures "d901" vertical distance of origin L5.end
  measures "d902" vertical distance of origin L7.end
extrude "Sloped T channel 3''" cut sketch "Sloped T channel 3 sketch (3)" along normal blind 236 bodies 7 in component "Vertical rail 2 - measured sloped-slot approximation"
ref_plane "WorkPlane6" through (0, 2, 0) normal (0, 1, 0) x (0, 0, 1) in component "Vertical rail 2 - measured sloped-slot approximation"
sketch "Reference center bore sketch (3)" plane through (0, 2, 0) normal (0, 1, 0) x (1, 0, 0) in component "Vertical rail 2 - measured sloped-slot approximation"
  circle A0 centre (228, -25) radius 2.5
  dimension "d907" = 228
  dimension "d908" = 25
  dimension "d909" = 5
  measures "d907" horizontal distance of origin A0.centre
  measures "d908" vertical distance of origin A0.centre
  measures "d909" diameter of A0
extrude "Reference center bore''" cut sketch "Reference center bore sketch (3)" along normal blind 236 bodies 7 in component "Vertical rail 2 - measured sloped-slot approximation"
ref_plane "WorkPlane1" through (22, 0, 0) normal (1, 0, 0) x (0, 1, 0) in component "Horizontal tie 00 - measured sloped-slot approximation"
sketch "Profile blank sketch (4)" plane through (22, 0, 0) normal (1, 0, 0) x (0, 0, -1) in component "Horizontal tie 00 - measured sloped-slot approximation"
  line L0 (-15, 2) -> (-15, 22)
  line L1 (-15, 22) -> (-35, 22)
  line L2 (-35, 22) -> (-35, 2)
  line L3 (-35, 2) -> (-15, 2)
  dimension "d914" = 15
  dimension "d915" = 2
  dimension "d916" = 22
  dimension "d917" = 35
  constraint vertical L0.start L0.end
  constraint horizontal L0.end L1.end
  constraint vertical L1.end L2.end
  constraint horizontal L0.start L2.end
  measures "d914" horizontal distance of origin L0.start
  measures "d915" vertical distance of origin L0.start
  measures "d916" vertical distance of origin L0.end
  measures "d917" horizontal distance of origin L1.end
extrude "Profile blank'''" add sketch "Profile blank sketch (4)" along normal blind 88 separate body makes body 8 in component "Horizontal tie 00 - measured sloped-slot approximation"
ref_plane "WorkPlane2" through (22, 0, 0) normal (1, 0, 0) x (0, 1, 0) in component "Horizontal tie 00 - measured sloped-slot approximation"